HX18-MG90S (Autodesk Fusion 360 design; units mm, degrees)
part number: 2026-10-09-00-45-20-548
part number: 2026-10-12-04-13-42-535
part number: 2026-10-12-04-13-44-447
part number: 2026-10-12-04-13-45-036
part number: 2026-10-12-04-13-46-302
part number: 2026-10-12-04-13-50-555
part number: 2026-10-12-04-13-50-831
part number: 2026-10-12-04-13-51-136
part number: 2026-10-12-04-13-51-421
part number: 2026-10-12-04-13-51-722
part number: 2026-10-12-04-13-52-037
part number: 2026-10-12-04-13-54-893
part number: 2026-10-12-04-13-57-107
part number: 2026-10-12-04-13-58-321
part number: 2026-10-12-04-14-00-599
part number: 2026-10-12-04-14-02-130
part number: 2026-10-12-04-14-04-108
part number: 2026-10-12-04-14-05-868
part number: 2026-10-12-04-14-07-389
part number: 2026-10-12-04-14-08-467
part number: 2026-10-12-04-14-30-689
part number: 2026-10-12-04-14-35-136
part number: 2026-10-12-04-14-39-838
part number: 2026-10-12-04-14-45-493
part number: 2026-10-12-04-14-51-238
part number: 2026-10-12-04-15-24-507
part number: 2026-10-12-04-15-29-782
part number: 2026-10-12-04-15-34-861
part number: 2026-10-12-04-15-38-571
part number: 2026-10-12-04-15-41-011
part number: 2026-10-12-04-15-42-765
part number: 2026-10-12-04-15-43-802
part number: 2026-10-12-04-16-17-546
part number: 2026-10-12-04-16-36-174
part number: 2026-10-12-04-16-55-944
Autodesk Fusion 360 part; units mm, degrees
(part 1 of 7)
sketch "Sketch1" plane through (0, 0, 0) normal (0, 0, 1) x (1, 0, 0)
  circle A0 centre (27.9831, 48.981) radius 25
  circle A1 centre (27.9831, 48.981) radius 20
  line L0 (12.3541, 68.4934) -> (43.2774, 29.2028)
  line L1 (12.3541, 68.4934) -> (-87.2317, -15.069)
  line L2 (43.2774, 29.2028) -> (-56.3084, -54.3596)
  line L3 (-87.2317, -15.069) -> (-56.3084, -54.3596) construction
  circle A2 centre (-71.7701, -34.7143) radius 25
  circle A3 centre (-71.7701, -34.7143) radius 20
  line L4 (-87.2317, -15.069) -> (-106.3828, -31.1387)
  line L5 (-87.2317, -15.069) -> (-15.2148, -15.069) construction
  line L6 (-56.3084, -54.3596) -> (-75.4595, -70.4293)
  line L7 (-56.3084, -54.3596) -> (15.7085, -54.3596) construction
  line L8 (-75.4595, -70.4293) -> (-93.9738, -175.4293)
  line L9 (-75.4595, -70.4293) -> (28.1658, -70.4293) construction
  line L10 (-93.9738, -175.4293) -> (-108.9738, -175.4293) construction
  line L11 (-108.9738, -175.4293) -> (-106.3828, -31.1387)
  circle A4 centre (-101.4738, -175.4293) radius 7.5
  dimension "d1" = 50
  dimension "d2" = -5
  dimension "d4" = 50
  dimension "d6" = 130
  dimension "d8" = 130
  dimension "d9" = -5
  dimension "d14" = 140
  dimension "d15" = 25
  dimension "d16" = 140
  dimension "d17" = 25
  dimension "d18" = 100
  dimension "d19" = 105
  dimension "d20" = 15
  constraint coincident A0 L0.start
  constraint midpoint L3 A2.centre
  constraint coincident L1.end A2
  constraint horizontal L5
  constraint horizontal L7
  constraint parallel L2 L6
  constraint horizontal L9
  constraint horizontal L10
  constraint midpoint L10 A4.centre
  constraint coincident L10.end A4
  measures "d1" diameter of A0
  measures "d4" distance of L0.start L0.end
  measures "d6" distance of L0.start L1.end
  measures "d8" distance of L0.end L2.end
  measures "d14" angle of L4 L5
  measures "d15" distance of L1.end L4.end
  measures "d16" angle of L6 L7
  measures "d17" distance of L2.end L6.end
  measures "d18" angle of L8 L9
  measures "d19" vertical distance of L6.end L8.end
  measures "d20" distance of L8.end L10.end
ref_plane "WorkPlane1" through (0, 0, -9) normal (0, 0, 1) x (1, 0, 0) in component "01 | Chassis · ground"
sketch "Hexagonal chassis" plane through (0, 0, -9) normal (0, 0, 1) x (1, 0, 0) in component "01 | Chassis · ground"
  line L0 (69, 0) -> (34.5, 59.7558)
  line L1 (34.5, 59.7558) -> (-34.5, 59.7558)
  line L2 (-34.5, 59.7558) -> (-69, 0)
  line L3 (-69, 0) -> (-34.5, -59.7558)
  line L4 (-34.5, -59.7558) -> (34.5, -59.7558)
  line L5 (34.5, -59.7558) -> (69, 0)
extrude "Hexagonal chassis (1)" add sketch "Hexagonal chassis" along normal blind 3 makes body 1 in component "01 | Chassis · ground"
ref_plane "WorkPlane2" through (0, 0, -9) normal (0, 0, 1) x (1, 0, 0) in component "01 | Chassis · ground"
sketch "Central wiring aperture" plane through (0, 0, -9) normal (0, 0, 1) x (1, 0, 0) in component "01 | Chassis · ground"
  line L0 (22, 0) -> (11, 19.0526)
  line L1 (11, 19.0526) -> (-11, 19.0526)
  line L2 (-11, 19.0526) -> (-22, 0)
  line L3 (-22, 0) -> (-11, -19.0526)
  line L4 (-11, -19.0526) -> (11, -19.0526)
  line L5 (11, -19.0526) -> (22, 0)
extrude "Central wiring aperture (1)" cut sketch "Central wiring aperture" along normal blind 3 bodies 1 in component "01 | Chassis · ground"
ref_plane "WorkPlane3" through (0, 0, -9) normal (0, 0, 1) x (1, 0, 0) in component "01 | Chassis · ground"
sketch "Yaw MG90S body clearance" plane through (0, 0, -9) normal (0, 0, 1) x (1, 0, 0) in component "01 | Chassis · ground"
  line L0 (32.7, -6.5) -> (56.1, -6.5)
  line L1 (56.1, -6.5) -> (56.1, 6.5)
  line L2 (56.1, 6.5) -> (32.7, 6.5)
  line L3 (32.7, 6.5) -> (32.7, -6.5)
extrude "Yaw MG90S body clearance (1)" cut sketch "Yaw MG90S body clearance" along normal blind 3 bodies 1 in component "01 | Chassis · ground"
ref_plane "WorkPlane4" through (0, 0, -9) normal (0, 0, 1) x (1, 0, 0) in component "01 | Chassis · ground"
sketch "Yaw ear fastener adjustment" plane through (0, 0, -9) normal (0, 0, 1) x (1, 0, 0) in component "01 | Chassis · ground"
  line L0 (31.6, -1.2) -> (31.9106, -1.1591)
  line L1 (31.9106, -1.1591) -> (32.2, -1.0392)
  line L2 (32.2, -1.0392) -> (32.4485, -0.8485)
  line L3 (32.4485, -0.8485) -> (32.6392, -0.6)
  line L4 (32.6392, -0.6) -> (32.7591, -0.3106)
  line L5 (32.7591, -0.3106) -> (32.8, 0)
  line L6 (32.8, 0) -> (32.7591, 0.3106)
  line L7 (32.7591, 0.3106) -> (32.6392, 0.6)
  line L8 (32.6392, 0.6) -> (32.4485, 0.8485)
  line L9 (32.4485, 0.8485) -> (32.2, 1.0392)
  line L10 (32.2, 1.0392) -> (31.9106, 1.1591)
  line L11 (31.9106, 1.1591) -> (31.6, 1.2)
  line L12 (31.6, 1.2) -> (29.4, 1.2)
  line L13 (29.4, 1.2) -> (29.0894, 1.1591)
  line L14 (29.0894, 1.1591) -> (28.8, 1.0392)
  line L15 (28.8, 1.0392) -> (28.5515, 0.8485)
  line L16 (28.5515, 0.8485) -> (28.3608, 0.6)
  line L17 (28.3608, 0.6) -> (28.2409, 0.3106)
  line L18 (28.2409, 0.3106) -> (28.2, 0)
  line L19 (28.2, 0) -> (28.2409, -0.3106)
  line L20 (28.2409, -0.3106) -> (28.3608, -0.6)
  line L21 (28.3608, -0.6) -> (28.5515, -0.8485)
  line L22 (28.5515, -0.8485) -> (28.8, -1.0392)
  line L23 (28.8, -1.0392) -> (29.0894, -1.1591)
  line L24 (29.0894, -1.1591) -> (29.4, -1.2)
  line L25 (29.4, -1.2) -> (31.6, -1.2)
  line L26 (59.4, -1.2) -> (59.7106, -1.1591)
  line L27 (59.7106, -1.1591) -> (60, -1.0392)
  line L28 (60, -1.0392) -> (60.2485, -0.8485)
  line L29 (60.2485, -0.8485) -> (60.4392, -0.6)
  line L30 (60.4392, -0.6) -> (60.5591, -0.3106)
  line L31 (60.5591, -0.3106) -> (60.6, 0)
  line L32 (60.6, 0) -> (60.5591, 0.3106)
  line L33 (60.5591, 0.3106) -> (60.4392, 0.6)
  line L34 (60.4392, 0.6) -> (60.2485, 0.8485)
  line L35 (60.2485, 0.8485) -> (60, 1.0392)
  line L36 (60, 1.0392) -> (59.7106, 1.1591)
  line L37 (59.7106, 1.1591) -> (59.4, 1.2)
  line L38 (59.4, 1.2) -> (57.2, 1.2)
  line L39 (57.2, 1.2) -> (56.8894, 1.1591)
  line L40 (56.8894, 1.1591) -> (56.6, 1.0392)
  line L41 (56.6, 1.0392) -> (56.3515, 0.8485)
  line L42 (56.3515, 0.8485) -> (56.1608, 0.6)
  line L43 (56.1608, 0.6) -> (56.0409, 0.3106)
  line L44 (56.0409, 0.3106) -> (56, 0)
  line L45 (56, 0) -> (56.0409, -0.3106)
  line L46 (56.0409, -0.3106) -> (56.1608, -0.6)
  line L47 (56.1608, -0.6) -> (56.3515, -0.8485)
  line L48 (56.3515, -0.8485) -> (56.6, -1.0392)
  line L49 (56.6, -1.0392) -> (56.8894, -1.1591)
  line L50 (56.8894, -1.1591) -> (57.2, -1.2)
  line L51 (57.2, -1.2) -> (59.4, -1.2)
extrude "Yaw ear fastener adjustment (1)" cut sketch "Yaw ear fastener adjustment" along normal blind 3 bodies 1 in component "01 | Chassis · ground"
ref_plane "WorkPlane5" through (0, 0, -9) normal (0, 0, 1) x (1, 0, 0) in component "01 | Chassis · ground"
sketch "M3 deck mounting" plane through (0, 0, -9) normal (0, 0, 1) x (1, 0, 0) in component "01 | Chassis · ground"
  circle A0 centre (27.7128, 16) radius 1.7
extrude "M3 deck mounting (1)" cut sketch "M3 deck mounting" along normal blind 3 bodies 1 in component "01 | Chassis · ground"
ref_plane "WorkPlane6" through (0, 0, -9) normal (0, 0, 1) x (1, 0, 0) in component "01 | Chassis · ground"
sketch "Yaw MG90S body clearance (1)" plane through (0, 0, -9) normal (0, 0, 1) x (1, 0, 0) in component "01 | Chassis · ground"
  line L0 (21.9792, 25.069) -> (33.6792, 45.334)
  line L1 (33.6792, 45.334) -> (22.4208, 51.834)
  line L2 (22.4208, 51.834) -> (10.7208, 31.569)
  line L3 (10.7208, 31.569) -> (21.9792, 25.069)
extrude "Yaw MG90S body clearance (2)" cut sketch "Yaw MG90S body clearance (1)" along normal blind 3 bodies 1 in component "01 | Chassis · ground"
ref_plane "WorkPlane7" through (0, 0, -9) normal (0, 0, 1) x (1, 0, 0) in component "01 | Chassis · ground"
sketch "Yaw ear fastener adjustment (1)" plane through (0, 0, -9) normal (0, 0, 1) x (1, 0, 0) in component "01 | Chassis · ground"
  line L0 (16.8392, 26.7664) -> (16.9591, 27.0558)
  line L1 (16.9591, 27.0558) -> (17, 27.3664)
  line L2 (17, 27.3664) -> (16.9591, 27.677)
  line L3 (16.9591, 27.677) -> (16.8392, 27.9664)
  line L4 (16.8392, 27.9664) -> (16.6485, 28.2149)
  line L5 (16.6485, 28.2149) -> (16.4, 28.4056)
  line L6 (16.4, 28.4056) -> (16.1106, 28.5255)
  line L7 (16.1106, 28.5255) -> (15.8, 28.5664)
  line L8 (15.8, 28.5664) -> (15.4894, 28.5255)
  line L9 (15.4894, 28.5255) -> (15.2, 28.4056)
  line L10 (15.2, 28.4056) -> (14.9515, 28.2149)
  line L11 (14.9515, 28.2149) -> (14.7608, 27.9664)
  line L12 (14.7608, 27.9664) -> (13.6608, 26.0611)
  line L13 (13.6608, 26.0611) -> (13.5409, 25.7717)
  line L14 (13.5409, 25.7717) -> (13.5, 25.4611)
  line L15 (13.5, 25.4611) -> (13.5409, 25.1506)
  line L16 (13.5409, 25.1506) -> (13.6608, 24.8611)
  line L17 (13.6608, 24.8611) -> (13.8515, 24.6126)
  line L18 (13.8515, 24.6126) -> (14.1, 24.4219)
  line L19 (14.1, 24.4219) -> (14.3894, 24.302)
  line L20 (14.3894, 24.302) -> (14.7, 24.2611)
  line L21 (14.7, 24.2611) -> (15.0106, 24.302)
  line L22 (15.0106, 24.302) -> (15.3, 24.4219)
  line L23 (15.3, 24.4219) -> (15.5485, 24.6126)
  line L24 (15.5485, 24.6126) -> (15.7392, 24.8611)
  line L25 (15.7392, 24.8611) -> (16.8392, 26.7664)
  line L26 (30.7392, 50.8419) -> (30.8591, 51.1313)
  line L27 (30.8591, 51.1313) -> (30.9, 51.4419)
  line L28 (30.9, 51.4419) -> (30.8591, 51.7525)
  line L29 (30.8591, 51.7525) -> (30.7392, 52.0419)
  line L30 (30.7392, 52.0419) -> (30.5485, 52.2904)
  line L31 (30.5485, 52.2904) -> (30.3, 52.4811)
  line L32 (30.3, 52.4811) -> (30.0106, 52.601)
  line L33 (30.0106, 52.601) -> (29.7, 52.6419)
  line L34 (29.7, 52.6419) -> (29.3894, 52.601)
  line L35 (29.3894, 52.601) -> (29.1, 52.4811)
  line L36 (29.1, 52.4811) -> (28.8515, 52.2904)
  line L37 (28.8515, 52.2904) -> (28.6608, 52.0419)
  line L38 (28.6608, 52.0419) -> (27.5608, 50.1367)
  line L39 (27.5608, 50.1367) -> (27.4409, 49.8472)
  line L40 (27.4409, 49.8472) -> (27.4, 49.5367)
  line L41 (27.4, 49.5367) -> (27.4409, 49.2261)
  line L42 (27.4409, 49.2261) -> (27.5608, 48.9367)
  line L43 (27.5608, 48.9367) -> (27.7515, 48.6881)
  line L44 (27.7515, 48.6881) -> (28, 48.4974)
  line L45 (28, 48.4974) -> (28.2894, 48.3775)
  line L46 (28.2894, 48.3775) -> (28.6, 48.3367)
  line L47 (28.6, 48.3367) -> (28.9106, 48.3775)
  line L48 (28.9106, 48.3775) -> (29.2, 48.4974)
  line L49 (29.2, 48.4974) -> (29.4485, 48.6881)
  line L50 (29.4485, 48.6881) -> (29.6392, 48.9367)
  line L51 (29.6392, 48.9367) -> (30.7392, 50.8419)
extrude "Yaw ear fastener adjustment (2)" cut sketch "Yaw ear fastener adjustment (1)" along normal blind 3 bodies 1 in component "01 | Chassis · ground"
ref_plane "WorkPlane8" through (0, 0, -9) normal (0, 0, 1) x (1, 0, 0) in component "01 | Chassis · ground"
sketch "M3 deck mounting (1)" plane through (0, 0, -9) normal (0, 0, 1) x (1, 0, 0) in component "01 | Chassis · ground"
  circle A0 centre (0, 32) radius 1.7
extrude "M3 deck mounting (2)" cut sketch "M3 deck mounting (1)" along normal blind 3 bodies 1 in component "01 | Chassis · ground"
ref_plane "WorkPlane9" through (0, 0, -9) normal (0, 0, 1) x (1, 0, 0) in component "01 | Chassis · ground"
sketch "Yaw MG90S body clearance (2)" plane through (0, 0, -9) normal (0, 0, 1) x (1, 0, 0) in component "01 | Chassis · ground"
  line L0 (-10.7208, 31.569) -> (-22.4208, 51.834)
  line L1 (-22.4208, 51.834) -> (-33.6792, 45.334)
  line L2 (-33.6792, 45.334) -> (-21.9792, 25.069)
  line L3 (-21.9792, 25.069) -> (-10.7208, 31.569)
extrude "Yaw MG90S body clearance (3)" cut sketch "Yaw MG90S body clearance (2)" along normal blind 3 bodies 1 in component "01 | Chassis · ground"
ref_plane "WorkPlane10" through (0, 0, -9) normal (0, 0, 1) x (1, 0, 0) in component "01 | Chassis · ground"
sketch "Yaw ear fastener adjustment (2)" plane through (0, 0, -9) normal (0, 0, 1) x (1, 0, 0) in component "01 | Chassis · ground"
  line L0 (-14.7608, 27.9664) -> (-14.9515, 28.2149)
  line L1 (-14.9515, 28.2149) -> (-15.2, 28.4056)
  line L2 (-15.2, 28.4056) -> (-15.4894, 28.5255)
  line L3 (-15.4894, 28.5255) -> (-15.8, 28.5664)
  line L4 (-15.8, 28.5664) -> (-16.1106, 28.5255)
  line L5 (-16.1106, 28.5255) -> (-16.4, 28.4056)
  line L6 (-16.4, 28.4056) -> (-16.6485, 28.2149)
  line L7 (-16.6485, 28.2149) -> (-16.8392, 27.9664)
  line L8 (-16.8392, 27.9664) -> (-16.9591, 27.677)
  line L9 (-16.9591, 27.677) -> (-17, 27.3664)
  line L10 (-17, 27.3664) -> (-16.9591, 27.0558)
  line L11 (-16.9591, 27.0558) -> (-16.8392, 26.7664)
  line L12 (-16.8392, 26.7664) -> (-15.7392, 24.8611)
  line L13 (-15.7392, 24.8611) -> (-15.5485, 24.6126)
  line L14 (-15.5485, 24.6126) -> (-15.3, 24.4219)
  line L15 (-15.3, 24.4219) -> (-15.0106, 24.302)
  line L16 (-15.0106, 24.302) -> (-14.7, 24.2611)
  line L17 (-14.7, 24.2611) -> (-14.3894, 24.302)
  line L18 (-14.3894, 24.302) -> (-14.1, 24.4219)
  line L19 (-14.1, 24.4219) -> (-13.8515, 24.6126)
  line L20 (-13.8515, 24.6126) -> (-13.6608, 24.8611)
  line L21 (-13.6608, 24.8611) -> (-13.5409, 25.1506)
  line L22 (-13.5409, 25.1506) -> (-13.5, 25.4611)
  line L23 (-13.5, 25.4611) -> (-13.5409, 25.7717)
  line L24 (-13.5409, 25.7717) -> (-13.6608, 26.0611)
  line L25 (-13.6608, 26.0611) -> (-14.7608, 27.9664)
  line L26 (-28.6608, 52.0419) -> (-28.8515, 52.2904)
  line L27 (-28.8515, 52.2904) -> (-29.1, 52.4811)
  line L28 (-29.1, 52.4811) -> (-29.3894, 52.601)
  line L29 (-29.3894, 52.601) -> (-29.7, 52.6419)
  line L30 (-29.7, 52.6419) -> (-30.0106, 52.601)
  line L31 (-30.0106, 52.601) -> (-30.3, 52.4811)
  line L32 (-30.3, 52.4811) -> (-30.5485, 52.2904)
  line L33 (-30.5485, 52.2904) -> (-30.7392, 52.0419)
  line L34 (-30.7392, 52.0419) -> (-30.8591, 51.7525)
  line L35 (-30.8591, 51.7525) -> (-30.9, 51.4419)
  line L36 (-30.9, 51.4419) -> (-30.8591, 51.1313)
  line L37 (-30.8591, 51.1313) -> (-30.7392, 50.8419)
  line L38 (-30.7392, 50.8419) -> (-29.6392, 48.9367)
  line L39 (-29.6392, 48.9367) -> (-29.4485, 48.6881)
  line L40 (-29.4485, 48.6881) -> (-29.2, 48.4974)
  line L41 (-29.2, 48.4974) -> (-28.9106, 48.3775)
  line L42 (-28.9106, 48.3775) -> (-28.6, 48.3367)
  line L43 (-28.6, 48.3367) -> (-28.2894, 48.3775)
  line L44 (-28.2894, 48.3775) -> (-28, 48.4974)
  line L45 (-28, 48.4974) -> (-27.7515, 48.6881)
  line L46 (-27.7515, 48.6881) -> (-27.5608, 48.9367)
  line L47 (-27.5608, 48.9367) -> (-27.4409, 49.2261)
  line L48 (-27.4409, 49.2261) -> (-27.4, 49.5367)
  line L49 (-27.4, 49.5367) -> (-27.4409, 49.8472)
  line L50 (-27.4409, 49.8472) -> (-27.5608, 50.1367)
  line L51 (-27.5608, 50.1367) -> (-28.6608, 52.0419)
extrude "Yaw ear fastener adjustment (3)" cut sketch "Yaw ear fastener adjustment (2)" along normal blind 3 bodies 1 in component "01 | Chassis · ground"
ref_plane "WorkPlane11" through (0, 0, -9) normal (0, 0, 1) x (1, 0, 0) in component "01 | Chassis · ground"
sketch "M3 deck mounting (2)" plane through (0, 0, -9) normal (0, 0, 1) x (1, 0, 0) in component "01 | Chassis · ground"
  circle A0 centre (-27.7128, 16) radius 1.7
extrude "M3 deck mounting (3)" cut sketch "M3 deck mounting (2)" along normal blind 3 bodies 1 in component "01 | Chassis · ground"
ref_plane "WorkPlane12" through (0, 0, -9) normal (0, 0, 1) x (1, 0, 0) in component "01 | Chassis · ground"
sketch "Yaw MG90S body clearance (3)" plane through (0, 0, -9) normal (0, 0, 1) x (1, 0, 0) in component "01 | Chassis · ground"
  line L0 (-32.7, 6.5) -> (-56.1, 6.5)
  line L1 (-56.1, 6.5) -> (-56.1, -6.5)
  line L2 (-56.1, -6.5) -> (-32.7, -6.5)
  line L3 (-32.7, -6.5) -> (-32.7, 6.5)
extrude "Yaw MG90S body clearance (4)" cut sketch "Yaw MG90S body clearance (3)" along normal blind 3 bodies 1 in component "01 | Chassis · ground"
ref_plane "WorkPlane13" through (0, 0, -9) normal (0, 0, 1) x (1, 0, 0) in component "01 | Chassis · ground"
sketch "Yaw ear fastener adjustment (3)" plane through (0, 0, -9) normal (0, 0, 1) x (1, 0, 0) in component "01 | Chassis · ground"
  line L0 (-31.6, 1.2) -> (-31.9106, 1.1591)
  line L1 (-31.9106, 1.1591) -> (-32.2, 1.0392)
  line L2 (-32.2, 1.0392) -> (-32.4485, 0.8485)
  line L3 (-32.4485, 0.8485) -> (-32.6392, 0.6)
  line L4 (-32.6392, 0.6) -> (-32.7591, 0.3106)
  line L5 (-32.7591, 0.3106) -> (-32.8, 0)
  line L6 (-32.8, 0) -> (-32.7591, -0.3106)
  line L7 (-32.7591, -0.3106) -> (-32.6392, -0.6)
  line L8 (-32.6392, -0.6) -> (-32.4485, -0.8485)
  line L9 (-32.4485, -0.8485) -> (-32.2, -1.0392)
  line L10 (-32.2, -1.0392) -> (-31.9106, -1.1591)
  line L11 (-31.9106, -1.1591) -> (-31.6, -1.2)
  line L12 (-31.6, -1.2) -> (-29.4, -1.2)
  line L13 (-29.4, -1.2) -> (-29.0894, -1.1591)
  line L14 (-29.0894, -1.1591) -> (-28.8, -1.0392)
  line L15 (-28.8, -1.0392) -> (-28.5515, -0.8485)
  line L16 (-28.5515, -0.8485) -> (-28.3608, -0.6)
  line L17 (-28.3608, -0.6) -> (-28.2409, -0.3106)
  line L18 (-28.2409, -0.3106) -> (-28.2, 0)
  line L19 (-28.2, 0) -> (-28.2409, 0.3106)
  line L20 (-28.2409, 0.3106) -> (-28.3608, 0.6)
  line L21 (-28.3608, 0.6) -> (-28.5515, 0.8485)
  line L22 (-28.5515, 0.8485) -> (-28.8, 1.0392)
  line L23 (-28.8, 1.0392) -> (-29.0894, 1.1591)
  line L24 (-29.0894, 1.1591) -> (-29.4, 1.2)
  line L25 (-29.4, 1.2) -> (-31.6, 1.2)
  line L26 (-59.4, 1.2) -> (-59.7106, 1.1591)
  line L27 (-59.7106, 1.1591) -> (-60, 1.0392)
  line L28 (-60, 1.0392) -> (-60.2485, 0.8485)
  line L29 (-60.2485, 0.8485) -> (-60.4392, 0.6)
  line L30 (-60.4392, 0.6) -> (-60.5591, 0.3106)
  line L31 (-60.5591, 0.3106) -> (-60.6, 0)
  line L32 (-60.6, 0) -> (-60.5591, -0.3106)
  line L33 (-60.5591, -0.3106) -> (-60.4392, -0.6)
  line L34 (-60.4392, -0.6) -> (-60.2485, -0.8485)
  line L35 (-60.2485, -0.8485) -> (-60, -1.0392)
  line L36 (-60, -1.0392) -> (-59.7106, -1.1591)
  line L37 (-59.7106, -1.1591) -> (-59.4, -1.2)
  line L38 (-59.4, -1.2) -> (-57.2, -1.2)
  line L39 (-57.2, -1.2) -> (-56.8894, -1.1591)
  line L40 (-56.8894, -1.1591) -> (-56.6, -1.0392)
  line L41 (-56.6, -1.0392) -> (-56.3515, -0.8485)
  line L42 (-56.3515, -0.8485) -> (-56.1608, -0.6)
  line L43 (-56.1608, -0.6) -> (-56.0409, -0.3106)
  line L44 (-56.0409, -0.3106) -> (-56, 0)
  line L45 (-56, 0) -> (-56.0409, 0.3106)
  line L46 (-56.0409, 0.3106) -> (-56.1608, 0.6)
  line L47 (-56.1608, 0.6) -> (-56.3515, 0.8485)
  line L48 (-56.3515, 0.8485) -> (-56.6, 1.0392)
  line L49 (-56.6, 1.0392) -> (-56.8894, 1.1591)
  line L50 (-56.8894, 1.1591) -> (-57.2, 1.2)
  line L51 (-57.2, 1.2) -> (-59.4, 1.2)
extrude "Yaw ear fastener adjustment (4)" cut sketch "Yaw ear fastener adjustment (3)" along normal blind 3 bodies 1 in component "01 | Chassis · ground"
ref_plane "WorkPlane14" through (0, 0, -9) normal (0, 0, 1) x (1, 0, 0) in component "01 | Chassis · ground"
sketch "M3 deck mounting (3)" plane through (0, 0, -9) normal (0, 0, 1) x (1, 0, 0) in component "01 | Chassis · ground"
  circle A0 centre (-27.7128, -16) radius 1.7
extrude "M3 deck mounting (4)" cut sketch "M3 deck mounting (3)" along normal blind 3 bodies 1 in component "01 | Chassis · ground"
ref_plane "WorkPlane15" through (0, 0, -9) normal (0, 0, 1) x (1, 0, 0) in component "01 | Chassis · ground"
sketch "Yaw MG90S body clearance (4)" plane through (0, 0, -9) normal (0, 0, 1) x (1, 0, 0) in component "01 | Chassis · ground"
  line L0 (-21.9792, -25.069) -> (-33.6792, -45.334)
  line L1 (-33.6792, -45.334) -> (-22.4208, -51.834)
  line L2 (-22.4208, -51.834) -> (-10.7208, -31.569)
  line L3 (-10.7208, -31.569) -> (-21.9792, -25.069)
extrude "Yaw MG90S body clearance (5)" cut sketch "Yaw MG90S body clearance (4)" along normal blind 3 bodies 1 in component "01 | Chassis · ground"
ref_plane "WorkPlane16" through (0, 0, -9) normal (0, 0, 1) x (1, 0, 0) in component "01 | Chassis · ground"
sketch "Yaw ear fastener adjustment (4)" plane through (0, 0, -9) normal (0, 0, 1) x (1, 0, 0) in component "01 | Chassis · ground"
  line L0 (-16.8392, -26.7664) -> (-16.9591, -27.0558)
  line L1 (-16.9591, -27.0558) -> (-17, -27.3664)
  line L2 (-17, -27.3664) -> (-16.9591, -27.677)
  line L3 (-16.9591, -27.677) -> (-16.8392, -27.9664)
  line L4 (-16.8392, -27.9664) -> (-16.6485, -28.2149)
  line L5 (-16.6485, -28.2149) -> (-16.4, -28.4056)
  line L6 (-16.4, -28.4056) -> (-16.1106, -28.5255)
  line L7 (-16.1106, -28.5255) -> (-15.8, -28.5664)
  line L8 (-15.8, -28.5664) -> (-15.4894, -28.5255)
  line L9 (-15.4894, -28.5255) -> (-15.2, -28.4056)
  line L10 (-15.2, -28.4056) -> (-14.9515, -28.2149)
  line L11 (-14.9515, -28.2149) -> (-14.7608, -27.9664)
  line L12 (-14.7608, -27.9664) -> (-13.6608, -26.0611)
  line L13 (-13.6608, -26.0611) -> (-13.5409, -25.7717)
  line L14 (-13.5409, -25.7717) -> (-13.5, -25.4611)
  line L15 (-13.5, -25.4611) -> (-13.5409, -25.1506)
  line L16 (-13.5409, -25.1506) -> (-13.6608, -24.8611)
  line L17 (-13.6608, -24.8611) -> (-13.8515, -24.6126)
  line L18 (-13.8515, -24.6126) -> (-14.1, -24.4219)
  line L19 (-14.1, -24.4219) -> (-14.3894, -24.302)
  line L20 (-14.3894, -24.302) -> (-14.7, -24.2611)
  line L21 (-14.7, -24.2611) -> (-15.0106, -24.302)
  line L22 (-15.0106, -24.302) -> (-15.3, -24.4219)
  line L23 (-15.3, -24.4219) -> (-15.5485, -24.6126)
  line L24 (-15.5485, -24.6126) -> (-15.7392, -24.8611)
  line L25 (-15.7392, -24.8611) -> (-16.8392, -26.7664)
  line L26 (-30.7392, -50.8419) -> (-30.8591, -51.1313)
  line L27 (-30.8591, -51.1313) -> (-30.9, -51.4419)
  line L28 (-30.9, -51.4419) -> (-30.8591, -51.7525)
  line L29 (-30.8591, -51.7525) -> (-30.7392, -52.0419)
  line L30 (-30.7392, -52.0419) -> (-30.5485, -52.2904)
  line L31 (-30.5485, -52.2904) -> (-30.3, -52.4811)
  line L32 (-30.3, -52.4811) -> (-30.0106, -52.601)
  line L33 (-30.0106, -52.601) -> (-29.7, -52.6419)
  line L34 (-29.7, -52.6419) -> (-29.3894, -52.601)
  line L35 (-29.3894, -52.601) -> (-29.1, -52.4811)
  line L36 (-29.1, -52.4811) -> (-28.8515, -52.2904)
  line L37 (-28.8515, -52.2904) -> (-28.6608, -52.0419)
  line L38 (-28.6608, -52.0419) -> (-27.5608, -50.1367)
  line L39 (-27.5608, -50.1367) -> (-27.4409, -49.8472)
  line L40 (-27.4409, -49.8472) -> (-27.4, -49.5367)
  line L41 (-27.4, -49.5367) -> (-27.4409, -49.2261)
  line L42 (-27.4409, -49.2261) -> (-27.5608, -48.9367)
  line L43 (-27.5608, -48.9367) -> (-27.7515, -48.6881)
  line L44 (-27.7515, -48.6881) -> (-28, -48.4974)
  line L45 (-28, -48.4974) -> (-28.2894, -48.3775)
  line L46 (-28.2894, -48.3775) -> (-28.6, -48.3367)
  line L47 (-28.6, -48.3367) -> (-28.9106, -48.3775)
  line L48 (-28.9106, -48.3775) -> (-29.2, -48.4974)
  line L49 (-29.2, -48.4974) -> (-29.4485, -48.6881)
  line L50 (-29.4485, -48.6881) -> (-29.6392, -48.9367)
  line L51 (-29.6392, -48.9367) -> (-30.7392, -50.8419)
extrude "Yaw ear fastener adjustment (5)" cut sketch "Yaw ear fastener adjustment (4)" along normal blind 3 bodies 1 in component "01 | Chassis · ground"
ref_plane "WorkPlane17" through (0, 0, -9) normal (0, 0, 1) x (1, 0, 0) in component "01 | Chassis · ground"
sketch "M3 deck mounting (4)" plane through (0, 0, -9) normal (0, 0, 1) x (1, 0, 0) in component "01 | Chassis · ground"
  circle A0 centre (0, -32) radius 1.7
extrude "M3 deck mounting (5)" cut sketch "M3 deck mounting (4)" along normal blind 3 bodies 1 in component "01 | Chassis · ground"
ref_plane "WorkPlane18" through (0, 0, -9) normal (0, 0, 1) x (1, 0, 0) in component "01 | Chassis · ground"
sketch "Yaw MG90S body clearance (5)" plane through (0, 0, -9) normal (0, 0, 1) x (1, 0, 0) in component "01 | Chassis · ground"
  line L0 (10.7208, -31.569) -> (22.4208, -51.834)
  line L1 (22.4208, -51.834) -> (33.6792, -45.334)
  line L2 (33.6792, -45.334) -> (21.9792, -25.069)
  line L3 (21.9792, -25.069) -> (10.7208, -31.569)
extrude "Yaw MG90S body clearance (6)" cut sketch "Yaw MG90S body clearance (5)" along normal blind 3 bodies 1 in component "01 | Chassis · ground"
ref_plane "WorkPlane19" through (0, 0, -9) normal (0, 0, 1) x (1, 0, 0) in component "01 | Chassis · ground"
sketch "Yaw ear fastener adjustment (5)" plane through (0, 0, -9) normal (0, 0, 1) x (1, 0, 0) in component "01 | Chassis · ground"
  line L0 (14.7608, -27.9664) -> (14.9515, -28.2149)
  line L1 (14.9515, -28.2149) -> (15.2, -28.4056)
  line L2 (15.2, -28.4056) -> (15.4894, -28.5255)
  line L3 (15.4894, -28.5255) -> (15.8, -28.5664)
  line L4 (15.8, -28.5664) -> (16.1106, -28.5255)
  line L5 (16.1106, -28.5255) -> (16.4, -28.4056)
  line L6 (16.4, -28.4056) -> (16.6485, -28.2149)
  line L7 (16.6485, -28.2149) -> (16.8392, -27.9664)
  line L8 (16.8392, -27.9664) -> (16.9591, -27.677)
  line L9 (16.9591, -27.677) -> (17, -27.3664)
  line L10 (17, -27.3664) -> (16.9591, -27.0558)
  line L11 (16.9591, -27.0558) -> (16.8392, -26.7664)
  line L12 (16.8392, -26.7664) -> (15.7392, -24.8611)
  line L13 (15.7392, -24.8611) -> (15.5485, -24.6126)
  line L14 (15.5485, -24.6126) -> (15.3, -24.4219)
  line L15 (15.3, -24.4219) -> (15.0106, -24.302)
  line L16 (15.0106, -24.302) -> (14.7, -24.2611)
  line L17 (14.7, -24.2611) -> (14.3894, -24.302)
  line L18 (14.3894, -24.302) -> (14.1, -24.4219)
  line L19 (14.1, -24.4219) -> (13.8515, -24.6126)
  line L20 (13.8515, -24.6126) -> (13.6608, -24.8611)
  line L21 (13.6608, -24.8611) -> (13.5409, -25.1506)
  line L22 (13.5409, -25.1506) -> (13.5, -25.4611)
  line L23 (13.5, -25.4611) -> (13.5409, -25.7717)
  line L24 (13.5409, -25.7717) -> (13.6608, -26.0611)
  line L25 (13.6608, -26.0611) -> (14.7608, -27.9664)
  line L26 (28.6608, -52.0419) -> (28.8515, -52.2904)
  line L27 (28.8515, -52.2904) -> (29.1, -52.4811)
  line L28 (29.1, -52.4811) -> (29.3894, -52.601)
  line L29 (29.3894, -52.601) -> (29.7, -52.6419)
  line L30 (29.7, -52.6419) -> (30.0106, -52.601)
  line L31 (30.0106, -52.601) -> (30.3, -52.4811)
  line L32 (30.3, -52.4811) -> (30.5485, -52.2904)
  line L33 (30.5485, -52.2904) -> (30.7392, -52.0419)
  line L34 (30.7392, -52.0419) -> (30.8591, -51.7525)
  line L35 (30.8591, -51.7525) -> (30.9, -51.4419)
  line L36 (30.9, -51.4419) -> (30.8591, -51.1313)
  line L37 (30.8591, -51.1313) -> (30.7392, -50.8419)
  line L38 (30.7392, -50.8419) -> (29.6392, -48.9367)
  line L39 (29.6392, -48.9367) -> (29.4485, -48.6881)
  line L40 (29.4485, -48.6881) -> (29.2, -48.4974)
  line L41 (29.2, -48.4974) -> (28.9106, -48.3775)
  line L42 (28.9106, -48.3775) -> (28.6, -48.3367)
  line L43 (28.6, -48.3367) -> (28.2894, -48.3775)
  line L44 (28.2894, -48.3775) -> (28, -48.4974)
  line L45 (28, -48.4974) -> (27.7515, -48.6881)
  line L46 (27.7515, -48.6881) -> (27.5608, -48.9367)
  line L47 (27.5608, -48.9367) -> (27.4409, -49.2261)
  line L48 (27.4409, -49.2261) -> (27.4, -49.5367)
  line L49 (27.4, -49.5367) -> (27.4409, -49.8472)
  line L50 (27.4409, -49.8472) -> (27.5608, -50.1367)
  line L51 (27.5608, -50.1367) -> (28.6608, -52.0419)
extrude "Yaw ear fastener adjustment (6)" cut sketch "Yaw ear fastener adjustment (5)" along normal blind 3 bodies 1 in component "01 | Chassis · ground"
ref_plane "WorkPlane20" through (0, 0, -9) normal (0, 0, 1) x (1, 0, 0) in component "01 | Chassis · ground"
sketch "M3 deck mounting (5)" plane through (0, 0, -9) normal (0, 0, 1) x (1, 0, 0) in component "01 | Chassis · ground"
  circle A0 centre (27.7128, -16) radius 1.7
extrude "M3 deck mounting (6)" cut sketch "M3 deck mounting (5)" along normal blind 3 bodies 1 in component "01 | Chassis · ground"
ref_plane "WorkPlane21" through (0, 0, -9) normal (0, 0, 1) x (1, 0, 0) in component "01 | Chassis · ground"
sketch "Lightening and cable window" plane through (0, 0, -9) normal (0, 0, 1) x (1, 0, 0) in component "01 | Chassis · ground"
  line L0 (35.409, 14.6699) -> (47.5333, 21.6699)
  line L1 (47.5333, 21.6699) -> (48.4974, 28)
  line L2 (48.4974, 28) -> (42.5333, 30.3301)
  line L3 (42.5333, 30.3301) -> (30.409, 23.3301)
  line L4 (30.409, 23.3301) -> (32.909, 19)
  line L5 (32.909, 19) -> (35.409, 14.6699)
extrude "Lightening and cable window (1)" cut sketch "Lightening and cable window" along normal blind 3 bodies 1 in component "01 | Chassis · ground"
ref_plane "WorkPlane22" through (0, 0, -9) normal (0, 0, 1) x (1, 0, 0) in component "01 | Chassis · ground"
sketch "Lightening and cable window (1)" plane through (0, 0, -9) normal (0, 0, 1) x (1, 0, 0) in component "01 | Chassis · ground"
  line L0 (5, 38) -> (5, 52)
  line L1 (5, 52) -> (0, 56)
  line L2 (0, 56) -> (-5, 52)
  line L3 (-5, 52) -> (-5, 38)
  line L4 (-5, 38) -> (0, 38)
  line L5 (0, 38) -> (5, 38)
extrude "Lightening and cable window (2)" cut sketch "Lightening and cable window (1)" along normal blind 3 bodies 1 in component "01 | Chassis · ground"
ref_plane "WorkPlane23" through (0, 0, -9) normal (0, 0, 1) x (1, 0, 0) in component "01 | Chassis · ground"
sketch "Lightening and cable window (2)" plane through (0, 0, -9) normal (0, 0, 1) x (1, 0, 0) in component "01 | Chassis · ground"
  line L0 (-30.409, 23.3301) -> (-42.5333, 30.3301)
  line L1 (-42.5333, 30.3301) -> (-48.4974, 28)
  line L2 (-48.4974, 28) -> (-47.5333, 21.6699)
  line L3 (-47.5333, 21.6699) -> (-35.409, 14.6699)
  line L4 (-35.409, 14.6699) -> (-32.909, 19)
  line L5 (-32.909, 19) -> (-30.409, 23.3301)
extrude "Lightening and cable window (3)" cut sketch "Lightening and cable window (2)" along normal blind 3 bodies 1 in component "01 | Chassis · ground"
ref_plane "WorkPlane24" through (0, 0, -9) normal (0, 0, 1) x (1, 0, 0) in component "01 | Chassis · ground"
sketch "Lightening and cable window (3)" plane through (0, 0, -9) normal (0, 0, 1) x (1, 0, 0) in component "01 | Chassis · ground"
  line L0 (-35.409, -14.6699) -> (-47.5333, -21.6699)
  line L1 (-47.5333, -21.6699) -> (-48.4974, -28)
  line L2 (-48.4974, -28) -> (-42.5333, -30.3301)
  line L3 (-42.5333, -30.3301) -> (-30.409, -23.3301)
  line L4 (-30.409, -23.3301) -> (-32.909, -19)
  line L5 (-32.909, -19) -> (-35.409, -14.6699)
extrude "Lightening and cable window (4)" cut sketch "Lightening and cable window (3)" along normal blind 3 bodies 1 in component "01 | Chassis · ground"
ref_plane "WorkPlane25" through (0, 0, -9) normal (0, 0, 1) x (1, 0, 0) in component "01 | Chassis · ground"
sketch "Lightening and cable window (4)" plane through (0, 0, -9) normal (0, 0, 1) x (1, 0, 0) in component "01 | Chassis · ground"
  line L0 (-5, -38) -> (-5, -52)
  line L1 (-5, -52) -> (0, -56)
  line L2 (0, -56) -> (5, -52)
  line L3 (5, -52) -> (5, -38)
  line L4 (5, -38) -> (0, -38)
  line L5 (0, -38) -> (-5, -38)
extrude "Lightening and cable window (5)" cut sketch "Lightening and cable window (4)" along normal blind 3 bodies 1 in component "01 | Chassis · ground"
ref_plane "WorkPlane26" through (0, 0, -9) normal (0, 0, 1) x (1, 0, 0) in component "01 | Chassis · ground"
sketch "Lightening and cable window (5)" plane through (0, 0, -9) normal (0, 0, 1) x (1, 0, 0) in component "01 | Chassis · ground"
  line L0 (30.409, -23.3301) -> (42.5333, -30.3301)
  line L1 (42.5333, -30.3301) -> (48.4974, -28)
  line L2 (48.4974, -28) -> (47.5333, -21.6699)
  line L3 (47.5333, -21.6699) -> (35.409, -14.6699)
  line L4 (35.409, -14.6699) -> (32.909, -19)
  line L5 (32.909, -19) -> (30.409, -23.3301)
extrude "Lightening and cable window (6)" cut sketch "Lightening and cable window (5)" along normal blind 3 bodies 1 in component "01 | Chassis · ground"
ref_plane "WorkPlane1" through (0, 0, -29) normal (0, 0, 1) x (1, 0, 0) in component "CORE | LowerDeck"
sketch "Battery tray base" plane through (0, 0, -29) normal (0, 0, 1) x (1, 0, 0) in component "CORE | LowerDeck"
  line L0 (37, 0) -> (36.6835, 4.6989)
  line L1 (36.6835, 4.6989) -> (35.7393, 9.3175)
  line L2 (35.7393, 9.3175) -> (34.1835, 13.7766)
  line L3 (34.1835, 13.7766) -> (32.0429, 18)
  line L4 (32.0429, 18) -> (29.3541, 21.9154)
  line L5 (29.3541, 21.9154) -> (26.163, 25.4558)
  line L6 (26.163, 25.4558) -> (22.5242, 28.5607)
  line L7 (22.5242, 28.5607) -> (18.5, 31.1769)
  line L8 (18.5, 31.1769) -> (14.1593, 33.2597)
  line L9 (14.1593, 33.2597) -> (9.5763, 34.7733)
  line L10 (9.5763, 34.7733) -> (4.8295, 35.692)
  line L11 (4.8295, 35.692) -> (0, 36)
  line L12 (0, 36) -> (-4.8295, 35.692)
  line L13 (-4.8295, 35.692) -> (-9.5763, 34.7733)
  line L14 (-9.5763, 34.7733) -> (-14.1593, 33.2597)
  line L15 (-14.1593, 33.2597) -> (-18.5, 31.1769)
  line L16 (-18.5, 31.1769) -> (-22.5242, 28.5607)
  line L17 (-22.5242, 28.5607) -> (-26.163, 25.4558)
  line L18 (-26.163, 25.4558) -> (-29.3541, 21.9154)
  line L19 (-29.3541, 21.9154) -> (-32.0429, 18)
  line L20 (-32.0429, 18) -> (-34.1835, 13.7766)
  line L21 (-34.1835, 13.7766) -> (-35.7393, 9.3175)
  line L22 (-35.7393, 9.3175) -> (-36.6835, 4.6989)
  line L23 (-36.6835, 4.6989) -> (-37, 0)
  line L24 (-37, 0) -> (-36.6835, -4.6989)
  line L25 (-36.6835, -4.6989) -> (-35.7393, -9.3175)
  line L26 (-35.7393, -9.3175) -> (-34.1835, -13.7766)
  line L27 (-34.1835, -13.7766) -> (-32.0429, -18)
  line L28 (-32.0429, -18) -> (-29.3541, -21.9154)
  line L29 (-29.3541, -21.9154) -> (-26.163, -25.4558)
  line L30 (-26.163, -25.4558) -> (-22.5242, -28.5607)
  line L31 (-22.5242, -28.5607) -> (-18.5, -31.1769)
  line L32 (-18.5, -31.1769) -> (-14.1593, -33.2597)
  line L33 (-14.1593, -33.2597) -> (-9.5763, -34.7733)
  line L34 (-9.5763, -34.7733) -> (-4.8295, -35.692)
  line L35 (-4.8295, -35.692) -> (0, -36)
  line L36 (0, -36) -> (4.8295, -35.692)
  line L37 (4.8295, -35.692) -> (9.5763, -34.7733)
  line L38 (9.5763, -34.7733) -> (14.1593, -33.2597)
  line L39 (14.1593, -33.2597) -> (18.5, -31.1769)
  line L40 (18.5, -31.1769) -> (22.5242, -28.5607)
  line L41 (22.5242, -28.5607) -> (26.163, -25.4558)
  line L42 (26.163, -25.4558) -> (29.3541, -21.9154)
  line L43 (29.3541, -21.9154) -> (32.0429, -18)
  line L44 (32.0429, -18) -> (34.1835, -13.7766)
  line L45 (34.1835, -13.7766) -> (35.7393, -9.3175)
  line L46 (35.7393, -9.3175) -> (36.6835, -4.6989)
  line L47 (36.6835, -4.6989) -> (37, 0)
extrude "Battery tray base (1)" add sketch "Battery tray base" along normal blind 3 separate body makes body 2 in component "CORE | LowerDeck"
ref_plane "WorkPlane2" through (0, 0, -29) normal (0, 0, 1) x (1, 0, 0) in component "CORE | LowerDeck"
sketch "M3 stack and 3mm battery strap slots" plane through (0, 0, -29) normal (0, 0, 1) x (1, 0, 0) in component "CORE | LowerDeck"
  circle A0 centre (27.7128, 16) radius 1.7
  circle A1 centre (0, 32) radius 1.7
  circle A2 centre (-27.7128, 16) radius 1.7
  circle A3 centre (-27.7128, -16) radius 1.7
  circle A4 centre (0, -32) radius 1.7
  circle A5 centre (27.7128, -16) radius 1.7
  line L0 (-23.5, 17) -> (-23.5511, 17.3882)
  line L1 (-23.5511, 17.3882) -> (-23.701, 17.75)
  line L2 (-23.701, 17.75) -> (-23.9393, 18.0607)
  line L3 (-23.9393, 18.0607) -> (-24.25, 18.299)
  line L4 (-24.25, 18.299) -> (-24.6118, 18.4489)
  line L5 (-24.6118, 18.4489) -> (-25, 18.5)
  line L6 (-25, 18.5) -> (-25.3882, 18.4489)
  line L7 (-25.3882, 18.4489) -> (-25.75, 18.299)
  line L8 (-25.75, 18.299) -> (-26.0607, 18.0607)
  line L9 (-26.0607, 18.0607) -> (-26.299, 17.75)
  line L10 (-26.299, 17.75) -> (-26.4489, 17.3882)
  line L11 (-26.4489, 17.3882) -> (-26.5, 17)
  line L12 (-26.5, 17) -> (-26.5, -17)
  line L13 (-26.5, -17) -> (-26.4489, -17.3882)
  line L14 (-26.4489, -17.3882) -> (-26.299, -17.75)
  line L15 (-26.299, -17.75) -> (-26.0607, -18.0607)
  line L16 (-26.0607, -18.0607) -> (-25.75, -18.299)
  line L17 (-25.75, -18.299) -> (-25.3882, -18.4489)
  line L18 (-25.3882, -18.4489) -> (-25, -18.5)
  line L19 (-25, -18.5) -> (-24.6118, -18.4489)
  line L20 (-24.6118, -18.4489) -> (-24.25, -18.299)
  line L21 (-24.25, -18.299) -> (-23.9393, -18.0607)
  line L22 (-23.9393, -18.0607) -> (-23.701, -17.75)
  line L23 (-23.701, -17.75) -> (-23.5511, -17.3882)
  line L24 (-23.5511, -17.3882) -> (-23.5, -17)
  line L25 (-23.5, -17) -> (-23.5, 17)
  line L26 (26.5, 17) -> (26.4489, 17.3882)
  line L27 (26.4489, 17.3882) -> (26.299, 17.75)
  line L28 (26.299, 17.75) -> (26.0607, 18.0607)
  line L29 (26.0607, 18.0607) -> (25.75, 18.299)
  line L30 (25.75, 18.299) -> (25.3882, 18.4489)
  line L31 (25.3882, 18.4489) -> (25, 18.5)
  line L32 (25, 18.5) -> (24.6118, 18.4489)
  line L33 (24.6118, 18.4489) -> (24.25, 18.299)
  line L34 (24.25, 18.299) -> (23.9393, 18.0607)
  line L35 (23.9393, 18.0607) -> (23.701, 17.75)
  line L36 (23.701, 17.75) -> (23.5511, 17.3882)
  line L37 (23.5511, 17.3882) -> (23.5, 17)
  line L38 (23.5, 17) -> (23.5, -17)
  line L39 (23.5, -17) -> (23.5511, -17.3882)
  line L40 (23.5511, -17.3882) -> (23.701, -17.75)
  line L41 (23.701, -17.75) -> (23.9393, -18.0607)
  line L42 (23.9393, -18.0607) -> (24.25, -18.299)
  line L43 (24.25, -18.299) -> (24.6118, -18.4489)
  line L44 (24.6118, -18.4489) -> (25, -18.5)
  line L45 (25, -18.5) -> (25.3882, -18.4489)
  line L46 (25.3882, -18.4489) -> (25.75, -18.299)
  line L47 (25.75, -18.299) -> (26.0607, -18.0607)
  line L48 (26.0607, -18.0607) -> (26.299, -17.75)
  line L49 (26.299, -17.75) -> (26.4489, -17.3882)
  line L50 (26.4489, -17.3882) -> (26.5, -17)
  line L51 (26.5, -17) -> (26.5, 17)
extrude "M3 stack and 3mm battery strap slots (1)" cut sketch "M3 stack and 3mm battery strap slots" along normal blind 3 bodies 2 in component "CORE | LowerDeck"
ref_plane "WorkPlane3" through (0, 0, -26) normal (0, 0, 1) x (1, 0, 0) in component "CORE | LowerDeck"
sketch "Battery corner guide" plane through (0, 0, -26) normal (0, 0, 1) x (1, 0, 0) in component "CORE | LowerDeck"
  line L0 (-24.5, -13.5) -> (-22.5, -13.5)
  line L1 (-22.5, -13.5) -> (-22.5, -8.5)
  line L2 (-22.5, -8.5) -> (-24.5, -8.5)
  line L3 (-24.5, -8.5) -> (-24.5, -13.5)
extrude "Battery corner guide (1)" add sketch "Battery corner guide" along normal blind 3 bodies 2 in component "CORE | LowerDeck"
ref_plane "WorkPlane4" through (0, 0, -26) normal (0, 0, 1) x (1, 0, 0) in component "CORE | LowerDeck"
sketch "Battery corner guide (1)" plane through (0, 0, -26) normal (0, 0, 1) x (1, 0, 0) in component "CORE | LowerDeck"
  line L0 (-24.5, 8.5) -> (-22.5, 8.5)
  line L1 (-22.5, 8.5) -> (-22.5, 13.5)
  line L2 (-22.5, 13.5) -> (-24.5, 13.5)
  line L3 (-24.5, 13.5) -> (-24.5, 8.5)
extrude "Battery corner guide (2)" add sketch "Battery corner guide (1)" along normal blind 3 bodies 2 in component "CORE | LowerDeck"
ref_plane "WorkPlane5" through (0, 0, -26) normal (0, 0, 1) x (1, 0, 0) in component "CORE | LowerDeck"
sketch "Battery corner guide (2)" plane through (0, 0, -26) normal (0, 0, 1) x (1, 0, 0) in component "CORE | LowerDeck"
  line L0 (22.5, -13.5) -> (24.5, -13.5)
  line L1 (24.5, -13.5) -> (24.5, -8.5)
  line L2 (24.5, -8.5) -> (22.5, -8.5)
  line L3 (22.5, -8.5) -> (22.5, -13.5)
extrude "Battery corner guide (3)" add sketch "Battery corner guide (2)" along normal blind 3 bodies 2 in component "CORE | LowerDeck"
ref_plane "WorkPlane6" through (0, 0, -26) normal (0, 0, 1) x (1, 0, 0) in component "CORE | LowerDeck"
sketch "Battery corner guide (3)" plane through (0, 0, -26) normal (0, 0, 1) x (1, 0, 0) in component "CORE | LowerDeck"
  line L0 (22.5, 8.5) -> (24.5, 8.5)
  line L1 (24.5, 8.5) -> (24.5, 13.5)
  line L2 (24.5, 13.5) -> (22.5, 13.5)
  line L3 (22.5, 13.5) -> (22.5, 8.5)
extrude "Battery corner guide (4)" add sketch "Battery corner guide (3)" along normal blind 3 bodies 2 in component "CORE | LowerDeck"
ref_plane "WorkPlane1" through (0, 0, -6) normal (0, 0, 1) x (1, 0, 0) in component "CORE | PowerShelf"
sketch "Ventilated regulator cradle" plane through (0, 0, -6) normal (0, 0, 1) x (1, 0, 0) in component "CORE | PowerShelf"
  line L0 (-18, -24) -> (18, -24)
  line L1 (18, -24) -> (18, 24)
  line L2 (18, 24) -> (-18, 24)
  line L3 (-18, 24) -> (-18, -24)
extrude "Ventilated regulator cradle (1)" add sketch "Ventilated regulator cradle" along normal blind 3 separate body makes body 3 in component "CORE | PowerShelf"
ref_plane "WorkPlane2" through (0, 0, -6) normal (0, 0, 1) x (1, 0, 0) in component "CORE | PowerShelf"
sketch "Stack support spoke" plane through (0, 0, -6) normal (0, 0, 1) x (1, 0, 0) in component "CORE | PowerShelf"
  line L0 (29.4628, 12.9689) -> (30.1877, 13.5251)
  line L1 (30.1877, 13.5251) -> (30.7439, 14.25)
  line L2 (30.7439, 14.25) -> (31.0936, 15.0941)
  line L3 (31.0936, 15.0941) -> (31.2128, 16)
  line L4 (31.2128, 16) -> (31.0936, 16.9059)
  line L5 (31.0936, 16.9059) -> (30.7439, 17.75)
  line L6 (30.7439, 17.75) -> (30.1877, 18.4749)
  line L7 (30.1877, 18.4749) -> (29.4628, 19.0311)
  line L8 (29.4628, 19.0311) -> (28.6187, 19.3807)
  line L9 (28.6187, 19.3807) -> (27.7128, 19.5)
  line L10 (27.7128, 19.5) -> (26.8069, 19.3807)
  line L11 (26.8069, 19.3807) -> (25.9628, 19.0311)
  line L12 (25.9628, 19.0311) -> (-1.75, 3.0311)
  line L13 (-1.75, 3.0311) -> (-2.4749, 2.4749)
  line L14 (-2.4749, 2.4749) -> (-3.0311, 1.75)
  line L15 (-3.0311, 1.75) -> (-3.3807, 0.9059)
  line L16 (-3.3807, 0.9059) -> (-3.5, 0)
  line L17 (-3.5, 0) -> (-3.3807, -0.9059)
  line L18 (-3.3807, -0.9059) -> (-3.0311, -1.75)
  line L19 (-3.0311, -1.75) -> (-2.4749, -2.4749)
  line L20 (-2.4749, -2.4749) -> (-1.75, -3.0311)
  line L21 (-1.75, -3.0311) -> (-0.9059, -3.3807)
  line L22 (-0.9059, -3.3807) -> (0, -3.5)
  line L23 (0, -3.5) -> (0.9059, -3.3807)
  line L24 (0.9059, -3.3807) -> (1.75, -3.0311)
  line L25 (1.75, -3.0311) -> (29.4628, 12.9689)
extrude "Stack support spoke (1)" add sketch "Stack support spoke" along normal blind 3 bodies 3 in component "CORE | PowerShelf"
ref_plane "WorkPlane3" through (0, 0, -6) normal (0, 0, 1) x (1, 0, 0) in component "CORE | PowerShelf"
sketch "Stack support spoke (1)" plane through (0, 0, -6) normal (0, 0, 1) x (1, 0, 0) in component "CORE | PowerShelf"
  line L0 (3.5, 32) -> (3.3807, 32.9059)
  line L1 (3.3807, 32.9059) -> (3.0311, 33.75)
  line L2 (3.0311, 33.75) -> (2.4749, 34.4749)
  line L3 (2.4749, 34.4749) -> (1.75, 35.0311)
  line L4 (1.75, 35.0311) -> (0.9059, 35.3807)
  line L5 (0.9059, 35.3807) -> (0, 35.5)
  line L6 (0, 35.5) -> (-0.9059, 35.3807)
  line L7 (-0.9059, 35.3807) -> (-1.75, 35.0311)
  line L8 (-1.75, 35.0311) -> (-2.4749, 34.4749)
  line L9 (-2.4749, 34.4749) -> (-3.0311, 33.75)
  line L10 (-3.0311, 33.75) -> (-3.3807, 32.9059)
  line L11 (-3.3807, 32.9059) -> (-3.5, 32)
  line L12 (-3.5, 32) -> (-3.5, 0)
  line L13 (-3.5, 0) -> (-3.3807, -0.9059)
  line L14 (-3.3807, -0.9059) -> (-3.0311, -1.75)
  line L15 (-3.0311, -1.75) -> (-2.4749, -2.4749)
  line L16 (-2.4749, -2.4749) -> (-1.75, -3.0311)
  line L17 (-1.75, -3.0311) -> (-0.9059, -3.3807)
  line L18 (-0.9059, -3.3807) -> (0, -3.5)
  line L19 (0, -3.5) -> (0.9059, -3.3807)
  line L20 (0.9059, -3.3807) -> (1.75, -3.0311)
  line L21 (1.75, -3.0311) -> (2.4749, -2.4749)
  line L22 (2.4749, -2.4749) -> (3.0311, -1.75)
  line L23 (3.0311, -1.75) -> (3.3807, -0.9059)
  line L24 (3.3807, -0.9059) -> (3.5, 0)
  line L25 (3.5, 0) -> (3.5, 32)
extrude "Stack support spoke (2)" add sketch "Stack support spoke (1)" along normal blind 3 bodies 3 in component "CORE | PowerShelf"
ref_plane "WorkPlane4" through (0, 0, -6) normal (0, 0, 1) x (1, 0, 0) in component "CORE | PowerShelf"
sketch "Stack support spoke (2)" plane through (0, 0, -6) normal (0, 0, 1) x (1, 0, 0) in component "CORE | PowerShelf"
  line L0 (-25.9628, 19.0311) -> (-26.8069, 19.3807)
  line L1 (-26.8069, 19.3807) -> (-27.7128, 19.5)
  line L2 (-27.7128, 19.5) -> (-28.6187, 19.3807)
  line L3 (-28.6187, 19.3807) -> (-29.4628, 19.0311)
  line L4 (-29.4628, 19.0311) -> (-30.1877, 18.4749)
  line L5 (-30.1877, 18.4749) -> (-30.7439, 17.75)
  line L6 (-30.7439, 17.75) -> (-31.0936, 16.9059)
  line L7 (-31.0936, 16.9059) -> (-31.2128, 16)
  line L8 (-31.2128, 16) -> (-31.0936, 15.0941)
  line L9 (-31.0936, 15.0941) -> (-30.7439, 14.25)
  line L10 (-30.7439, 14.25) -> (-30.1877, 13.5251)
  line L11 (-30.1877, 13.5251) -> (-29.4628, 12.9689)
  line L12 (-29.4628, 12.9689) -> (-1.75, -3.0311)
  line L13 (-1.75, -3.0311) -> (-0.9059, -3.3807)
  line L14 (-0.9059, -3.3807) -> (0, -3.5)
  line L15 (0, -3.5) -> (0.9059, -3.3807)
  line L16 (0.9059, -3.3807) -> (1.75, -3.0311)
  line L17 (1.75, -3.0311) -> (2.4749, -2.4749)
  line L18 (2.4749, -2.4749) -> (3.0311, -1.75)
  line L19 (3.0311, -1.75) -> (3.3807, -0.9059)
  line L20 (3.3807, -0.9059) -> (3.5, 0)
  line L21 (3.5, 0) -> (3.3807, 0.9059)
  line L22 (3.3807, 0.9059) -> (3.0311, 1.75)
  line L23 (3.0311, 1.75) -> (2.4749, 2.4749)
  line L24 (2.4749, 2.4749) -> (1.75, 3.0311)
  line L25 (1.75, 3.0311) -> (-25.9628, 19.0311)
extrude "Stack support spoke (3)" add sketch "Stack support spoke (2)" along normal blind 3 bodies 3 in component "CORE | PowerShelf"
ref_plane "WorkPlane5" through (0, 0, -6) normal (0, 0, 1) x (1, 0, 0) in component "CORE | PowerShelf"
sketch "Stack support spoke (3)" plane through (0, 0, -6) normal (0, 0, 1) x (1, 0, 0) in component "CORE | PowerShelf"
  line L0 (-29.4628, -12.9689) -> (-30.1877, -13.5251)
  line L1 (-30.1877, -13.5251) -> (-30.7439, -14.25)
  line L2 (-30.7439, -14.25) -> (-31.0936, -15.0941)
  line L3 (-31.0936, -15.0941) -> (-31.2128, -16)
  line L4 (-31.2128, -16) -> (-31.0936, -16.9059)
  line L5 (-31.0936, -16.9059) -> (-30.7439, -17.75)
  line L6 (-30.7439, -17.75) -> (-30.1877, -18.4749)
  line L7 (-30.1877, -18.4749) -> (-29.4628, -19.0311)
  line L8 (-29.4628, -19.0311) -> (-28.6187, -19.3807)
  line L9 (-28.6187, -19.3807) -> (-27.7128, -19.5)
  line L10 (-27.7128, -19.5) -> (-26.8069, -19.3807)
  line L11 (-26.8069, -19.3807) -> (-25.9628, -19.0311)
  line L12 (-25.9628, -19.0311) -> (1.75, -3.0311)
  line L13 (1.75, -3.0311) -> (2.4749, -2.4749)
  line L14 (2.4749, -2.4749) -> (3.0311, -1.75)
  line L15 (3.0311, -1.75) -> (3.3807, -0.9059)
  line L16 (3.3807, -0.9059) -> (3.5, 0)
  line L17 (3.5, 0) -> (3.3807, 0.9059)
  line L18 (3.3807, 0.9059) -> (3.0311, 1.75)
  line L19 (3.0311, 1.75) -> (2.4749, 2.4749)
  line L20 (2.4749, 2.4749) -> (1.75, 3.0311)
  line L21 (1.75, 3.0311) -> (0.9059, 3.3807)
  line L22 (0.9059, 3.3807) -> (0, 3.5)
  line L23 (0, 3.5) -> (-0.9059, 3.3807)
  line L24 (-0.9059, 3.3807) -> (-1.75, 3.0311)
  line L25 (-1.75, 3.0311) -> (-29.4628, -12.9689)
extrude "Stack support spoke (4)" add sketch "Stack support spoke (3)" along normal blind 3 bodies 3 in component "CORE | PowerShelf"
ref_plane "WorkPlane6" through (0, 0, -6) normal (0, 0, 1) x (1, 0, 0) in component "CORE | PowerShelf"
sketch "Stack support spoke (4)" plane through (0, 0, -6) normal (0, 0, 1) x (1, 0, 0) in component "CORE | PowerShelf"
  line L0 (-3.5, -32) -> (-3.3807, -32.9059)
  line L1 (-3.3807, -32.9059) -> (-3.0311, -33.75)
  line L2 (-3.0311, -33.75) -> (-2.4749, -34.4749)
  line L3 (-2.4749, -34.4749) -> (-1.75, -35.0311)
  line L4 (-1.75, -35.0311) -> (-0.9059, -35.3807)
  line L5 (-0.9059, -35.3807) -> (0, -35.5)
  line L6 (0, -35.5) -> (0.9059, -35.3807)
  line L7 (0.9059, -35.3807) -> (1.75, -35.0311)
  line L8 (1.75, -35.0311) -> (2.4749, -34.4749)
  line L9 (2.4749, -34.4749) -> (3.0311, -33.75)
  line L10 (3.0311, -33.75) -> (3.3807, -32.9059)
  line L11 (3.3807, -32.9059) -> (3.5, -32)
  line L12 (3.5, -32) -> (3.5, 0)
  line L13 (3.5, 0) -> (3.3807, 0.9059)
  line L14 (3.3807, 0.9059) -> (3.0311, 1.75)
  line L15 (3.0311, 1.75) -> (2.4749, 2.4749)
  line L16 (2.4749, 2.4749) -> (1.75, 3.0311)
  line L17 (1.75, 3.0311) -> (0.9059, 3.3807)
  line L18 (0.9059, 3.3807) -> (0, 3.5)
  line L19 (0, 3.5) -> (-0.9059, 3.3807)
  line L20 (-0.9059, 3.3807) -> (-1.75, 3.0311)
  line L21 (-1.75, 3.0311) -> (-2.4749, 2.4749)
  line L22 (-2.4749, 2.4749) -> (-3.0311, 1.75)
  line L23 (-3.0311, 1.75) -> (-3.3807, 0.9059)
  line L24 (-3.3807, 0.9059) -> (-3.5, 0)
  line L25 (-3.5, 0) -> (-3.5, -32)
extrude "Stack support spoke (5)" add sketch "Stack support spoke (4)" along normal blind 3 bodies 3 in component "CORE | PowerShelf"
ref_plane "WorkPlane7" through (0, 0, -6) normal (0, 0, 1) x (1, 0, 0) in component "CORE | PowerShelf"